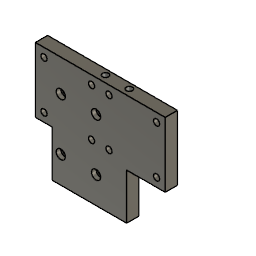
Extruder-mount (Autodesk Fusion 360 design; units mm, degrees)
Autodesk Fusion 360 part; units mm, degrees
sketch "Skizze1" plane through (0, 0, 0) normal (0, 0, 1) x (1, 0, 0)
  line L0 (-17.0646, 19.42) -> (67.5354, 19.42)
  line L1 (67.5354, 19.42) -> (67.5354, -22.88)
  line L2 (-17.0646, -22.88) -> (-17.0646, 19.42)
  circle A0 centre (-11.4146, 13.77) radius 2
  circle A1 centre (-11.4146, -17.23) radius 2
  circle A2 centre (61.8854, -17.23) radius 2
  circle A3 centre (61.8854, 13.77) radius 2
  circle A4 centre (19.5854, 13.77) radius 2
  circle A5 centre (19.5854, -17.23) radius 2
  circle A6 centre (30.8854, 13.77) radius 2
  circle A7 centre (30.8854, -17.23) radius 2
  circle A8 centre (-0.5146, -1.43) radius 1.65
  circle A9 centre (-0.5146, -35.43) radius 1.65
  line L3 (42.3854, -52.88) -> (-6.1646, -52.88)
  circle A10 centre (22.4854, -1.43) radius 1.65
  circle A11 centre (22.4854, -35.43) radius 1.65
  circle A12 centre (-0.5146, -1.43) radius 3
  circle A13 centre (22.4854, -1.43) radius 3
  circle A14 centre (22.4854, -35.43) radius 3
  circle A15 centre (-0.5146, -35.43) radius 3
  circle A16 centre (-11.4146, 13.77) radius 1.65
  circle A17 centre (-11.4146, -17.23) radius 1.65
  circle A18 centre (19.5854, -17.23) radius 1.65
  circle A19 centre (19.5854, 13.77) radius 1.65
  circle A20 centre (30.8854, 13.77) radius 1.65
  circle A21 centre (30.8854, -17.23) radius 1.65
  circle A22 centre (61.8854, -17.23) radius 1.65
  circle A23 centre (61.8854, 13.77) radius 1.65
  line L4 (-6.1646, -52.88) -> (-6.1646, -22.88)
  line L5 (-6.1646, -22.88) -> (-17.0646, -22.88)
  line L6 (42.3854, -52.88) -> (42.3854, -22.88)
  line L7 (42.3854, -22.88) -> (67.5354, -22.88)
  dimension "d1" = 84.6
  dimension "d2" = 42.3
  dimension "d3" = 4
  dimension "d4" = 5.65
  dimension "d5" = 5.65
  dimension "d6" = 4
  dimension "d8" = 5.65
  dimension "d9" = 3.3
  dimension "d12" = 3.3
  dimension "d14" = 34
  dimension "d15" = 18.2
  dimension "d16" = 4
  dimension "d18" = 5.65
  dimension "d20" = 31
  dimension "d21" = 31
  dimension "d22" = 5.65
  dimension "d23" = 4
  dimension "d25" = 4
  dimension "d27" = 31
  dimension "d28" = 31
  dimension "d29" = 5.65
  dimension "d30" = 5.65
  dimension "d31" = 5.65
  dimension "d32" = 16.55
  dimension "d35" = 3.3
  dimension "d36" = 23
  dimension "d37" = 3.3
  dimension "d38" = 23
  dimension "d39" = 18.2
  dimension "d40" = 34
  dimension "d41" = 35.65
  dimension "d51" = 4
  dimension "d52" = 6
  dimension "d53" = 6
  dimension "d54" = 6
  dimension "d55" = 6
  dimension "d56" = 3.3
  dimension "d57" = 3.3
  dimension "d58" = 3.3
  dimension "d59" = 3.3
  dimension "d60" = 3.3
  dimension "d61" = 3.3
  dimension "d62" = 3.3
  dimension "d63" = 3.3
  dimension "d109" = 10.9
  dimension "d111" = 48.55
  dimension "d113" = 25.15
  dimension "d114" = 42.3
  dimension "d115" = 25.75
  dimension "d125" = 30
  constraint horizontal L0
  constraint vertical L1
  constraint vertical L2
  constraint horizontal L3
  constraint concentric A8 A12
  constraint concentric A10 A13
  constraint concentric A11 A14
  constraint concentric A9 A15
  constraint concentric A0 A16
  constraint concentric A1 A17
  constraint concentric A5 A18
  constraint concentric A4 A19
  constraint concentric A6 A20
  constraint concentric A7 A21
  constraint concentric A2 A22
  constraint concentric A3 A23
  constraint vertical L4
  constraint horizontal L5
  constraint vertical L6
  constraint horizontal L7
  constraint coincident L2.start L5
  measures "d1" distance of L0.start L0.end
  measures "d2" distance of L0.start L2.start
  measures "d3" diameter of A0
  measures "d4" distance of L0 A0.centre
  measures "d5" distance of L2 A0.centre
  measures "d6" diameter of A4
  measures "d8" distance of L0 A4.centre
  measures "d9" diameter of A8
  measures "d12" diameter of A9
  measures "d14" distance of A8.centre A9.centre
  measures "d15" vertical distance of A5.centre A9.centre
  measures "d16" diameter of A1
  measures "d18" distance of L2 A1.centre
  measures "d20" distance of A1.centre A5.centre
  measures "d21" distance of A0.centre A4.centre
  measures "d22" distance of L1 A2.centre
  measures "d23" diameter of A2
  measures "d25" diameter of A7
  measures "d27" distance of A2.centre A7.centre
  measures "d28" distance of A3.centre A6.centre
  measures "d29" distance of L0 A3.centre
  measures "d30" distance of L1 A3.centre
  measures "d31" distance of L0 A6.centre
  measures "d32" distance of L2 A8.centre
  measures "d35" diameter of A10
  measures "d36" horizontal distance of A8.centre A10.centre
  measures "d37" diameter of A11
  measures "d38" horizontal distance of A9.centre A11.centre
  measures "d39" vertical distance of A7.centre A11.centre
  measures "d40" distance of A10.centre A11.centre
  measures "d41" distance of A1.centre L3
  measures "d51" diameter of A5
  measures "d52" diameter of A12
  measures "d53" diameter of A13
  measures "d54" diameter of A14
  measures "d55" diameter of A15
  measures "d56" diameter of A16
  measures "d57" diameter of A17
  measures "d58" diameter of A18
  measures "d59" diameter of A19
  measures "d60" diameter of A20
  measures "d61" diameter of A21
  measures "d62" diameter of A22
  measures "d63" diameter of A23
  measures "d109" distance of L4.end L2.start
  measures "d111" distance of L3.end L3.start
  measures "d113" distance of L6.end L1.end
  measures "d114" distance of L0.end L1.end
  measures "d115" distance of A5.centre L4
  measures "d125" distance of L3.start L6.end
extrude "Extrusion3" add sketch "Skizze1" along normal blind 8 contours L0 L1 L2 L3 L4 L5 L6 L7
extrude "Extrusion4" add sketch "Skizze1" along normal blind 1.3 contours A1
extrude "Extrusion5" add sketch "Skizze1" along normal blind 1.3 contours A0 | A2 | A3 | A4 | A5 | A6 | A7
extrude "Extrusion6" add sketch "Skizze1" along normal blind 5 contours A12 | A13 | A14 | A15
move_body "Verschieben1" bodies 1 to x (1, 0, 0) y (0, 0, 1) z (0, -1, 0) at (5.4916, -43.3069, 53.4228)
sketch "Skizze2" plane through (0, -43.3069, 0) normal (0, 1, 0) x (-1, 0, 0)
  circle A0 centre (-4.977, 51.9928) radius 1.65
  circle A1 centre (-27.977, 51.9928) radius 1.65
  circle A2 centre (-4.977, 17.9928) radius 1.65
  circle A3 centre (-27.977, 17.9928) radius 1.65
  circle A4 centre (-25.077, 36.1928) radius 1.65
  circle A5 centre (-36.377, 67.1928) radius 1.65
  circle A6 centre (-67.377, 67.1928) radius 1.65
  circle A7 centre (-36.377, 36.1928) radius 1.65
  circle A8 centre (-25.077, 67.1928) radius 1.65
  circle A9 centre (-67.377, 36.1928) radius 1.65
  circle A10 centre (5.923, 67.1928) radius 1.65
  line L0 (-47.877, 0.5428) -> (0.673, 0.5428)
  line L1 (11.573, 30.5428) -> (11.573, 72.8428)
  line L2 (11.573, 72.8428) -> (-73.027, 72.8428)
  line L3 (-73.027, 72.8428) -> (-73.027, 30.5428)
  line L4 (-0.977, 41.9928) -> (10.823, 41.9928)
  line L5 (10.823, 41.9928) -> (10.823, 34.9928)
  line L6 (10.823, 34.9928) -> (-0.977, 34.9928)
  line L7 (-0.977, 34.9928) -> (-0.977, 41.9928)
  line L8 (-47.877, 30.5428) -> (-47.877, 0.5428)
  line L9 (0.673, 0.5428) -> (0.673, 30.5428)
  line L10 (0.673, 30.5428) -> (11.573, 30.5428)
  line L11 (-73.027, 30.5428) -> (-47.877, 30.5428)
  dimension "d72" = 11.8
  dimension "d73" = 7
  dimension "d74" = 4
  dimension "d76" = 17
  constraint horizontal L4
  constraint vertical L5
  constraint horizontal L6
  constraint vertical L7
  measures "d72" distance of L4.start L4.end
  measures "d73" distance of L4.start L6.end
  measures "d74" distance of A2.centre L7
  measures "d76" distance of A2.centre L6
extrude "Extrusion9" add sketch "Skizze2" along normal blind 28.1 contours L4 L5 L6 L7
extrude "Extrusion10" add sketch "Skizze2" along normal blind 28.1 contours L4 L5 L6 L7
sketch "Skizze4" plane through (0, 0, 41.9928) normal (0, 0, 1) x (-1, 0, 0)
  line L0 (10.823, 43.3069) -> (-0.977, 43.3069)
  line L1 (-0.977, 43.3069) -> (-0.977, 15.2069)
  line L2 (-0.977, 15.2069) -> (10.823, 15.2069)
  line L3 (10.823, 15.2069) -> (10.823, 43.3069)
  circle A0 centre (4.823, 19.2069) radius 2
  circle A1 centre (4.823, 37.2069) radius 2
  dimension "d98" = 4
  dimension "d99" = 4
  dimension "d100" = 5.8
  dimension "d101" = 4
  dimension "d116" = 5.8
  dimension "d117" = 18
  measures "d98" diameter of A0
  measures "d99" distance of L2 A0.centre
  measures "d100" distance of L1 A0.centre
  measures "d101" diameter of A1
  measures "d116" distance of L1 A1.centre
  measures "d117" distance of A0.centre A1.centre
extrude "Extrusion13" cut sketch "Skizze4" against normal blind 8 contours A0 | A1
sketch "Skizze5" plane through (-10.823, 0, 0) normal (-1, 0, 0) x (0, -1, 0)
  line L0 (43.3069, 34.9928) -> (43.3069, 41.9928)
  line L1 (43.3069, 41.9928) -> (15.2069, 41.9928)
  line L2 (15.2069, 41.9928) -> (15.2069, 34.9928)
  line L3 (15.2069, 34.9928) -> (43.3069, 34.9928)
  line L4 (15.2069, 41.9928) -> (43.3262, 69.0993)
  line L5 (22.6632, 41.9928) -> (43.3262, 61.9116)
  line L6 (15.2069, 41.9928) -> (22.6632, 41.9928)
  line L7 (43.3262, 69.0993) -> (43.3262, 61.9116)
  constraint coincident L1.end L2.start
  constraint coincident L1 L5.start
  constraint vertical L7
extrude "Extrusion14" add sketch "Skizze5" against normal blind 11.8 contours L1 L4 L5 L6 L7
sketch "Skizze6" plane through (0, 0, 72.8428) normal (0, 0, 1) x (-1, 0, 0)
  line L0 (-73.027, 43.3069) -> (11.573, 43.3069)
  line L1 (11.573, 43.3069) -> (11.573, 51.3069)
  line L2 (11.573, 51.3069) -> (-73.027, 51.3069)
  line L3 (-73.027, 51.3069) -> (-73.027, 43.3069)
  line L4 (-73.027, 51.3069) -> (11.573, 51.3069)
  line L5 (11.573, 51.3069) -> (11.573, 43.3069)
  line L6 (11.573, 43.3069) -> (-73.027, 43.3069)
  line L7 (-73.027, 43.3069) -> (-73.027, 51.3069)
  circle A0 centre (-45.227, 46.9069) radius 2
  circle A1 centre (-29.727, 46.9069) radius 2
  dimension "d118" = 4
  dimension "d119" = 4
  dimension "d120" = 15.5
  dimension "d121" = 27.8
  dimension "d122" = 3.6
  constraint horizontal L4
  constraint vertical L5
  constraint horizontal L6
  constraint vertical L7
  constraint coincident L0.end L1.start
  constraint coincident L2.end L3.start
  measures "d118" diameter of A0
  measures "d119" diameter of A1
  measures "d120" distance of A0.centre A1.centre
  measures "d121" distance of L7 A0.centre
  measures "d122" distance of L6 A1.centre
extrude "Extrusion15" cut sketch "Skizze6" against normal blind 5.7 contours A0 | A1
